Autodesk Fusion 360 part; units mm, degrees
(part 2 of 2)
equation "lin_gap_Ref = 4 mm" comment "ASSUMPTION: PM ruling pass C: gap above the upper side linings so they stay floating (= the 4 mm stack gap)"
equation "seam_gap_Ref = 2.26 mm" comment "DECIDED: PM ruling 2026-10-31 (Mechanical Checker F-001, F-005): the Joints Engineer's 2.26 mm at all nine site seam types, set by a metal stop (1.5 stop washer + 0.76 rivnut head; joints register section 2.8)"
equation "wall_z0_Ref = glide_h_Ref + band_h_Ref" comment "CALCULATION: base band top: glides + band"
equation "panel_z0_Ref = wall_z0_Ref + seam_gap_Ref" comment "CALCULATION: walls stand one seam_gap above the band top (joints register 2.8, IF-01)"
equation "wall_h_Ref = pod_h_Ref - wall_z0_Ref" comment "CALCULATION: 2290 = layout study v2_model wall_h"
equation "side_h_Ref = ( wall_h_Ref - 2 * seam_gap_Ref ) / 2" comment "CALCULATION: D-23: 2 sheets per side wall; the gap on the band and the horizontal seam (joints register 2.8)"
equation "back_oh_Ref = pod_h_Ref - outer_t_Ref - seam_gap_Ref - panel_z0_Ref" comment "CALCULATION: PM ruling 2026-10-31 (pass D, F-004): the back outer frames run up to the ceiling frame (pod_h - outer_t), less the seam_gap under it, closing the slot at the back top edge"
equation "back_ph_Ref = ( back_oh_Ref - seam_gap_Ref ) / 2" comment "CALCULATION: D-23: 4 sheets on the back, two equal rows with one seam_gap between them (joints register 2.8); the lower back linings match the lower row, as on the side walls"
equation "n_base_bolt_Ref = 4" comment "DECIDED: PM ruling 2026-10-31, J-BASE-01: bolts per panel along the band, evenly spaced"
equation "skin_t_Ref = 3 mm" comment "DECIDED: ACP skin, walls and ceiling (D-16; PM ruling 2026-10-31 on outer_t)"
equation "bond_t_Ref = 3 mm" comment "DECIDED: bond line between the ACP and the frame (PM ruling 2026-10-31 on outer_t)"
equation "frame_t_Ref = 40 mm" comment "DECIDED: aluminium frame tube depth, walls and ceiling (PM ruling 2026-10-31 on outer_t)"
equation "bolt_edge_inset_Ref = 220 mm" comment "DECIDED: PM ruling 2026-10-31: on every bolted edge the end bolts sit this far in from each panel end (the FRAME end, where the bolts go), the rest evenly spaced"
equation "spigot_inset_Ref = 100 mm" comment "DECIDED: PM ruling 2026-10-31: locating spigots this far in from each panel end (round hole at one end, slot at the other)"
equation "ceil_bolt_z_Ref = pod_h_Ref - outer_t_Ref + frame_t_Ref / 2" comment "DECIDED: PM ruling 2026-10-31, J-CEIL-01 wall to ceiling: the bolt line on the ceiling frame's centre (Z 2374)"
equation "pod_w = pod_w_Ref" comment "LINKED: pod_w_Ref, derived from 100000_P04_POD-SKELETON_CAD v4 (skeleton is the single source)"
equation "pod_d = pod_d_Ref" comment "LINKED: pod_d_Ref, derived from 100000_P04_POD-SKELETON_CAD v4 (skeleton is the single source)"
equation "pod_h = pod_h_Ref" comment "LINKED: pod_h_Ref, derived from 100000_P04_POD-SKELETON_CAD v4 (skeleton is the single source)"
equation "wall_depth = wall_depth_Ref" comment "LINKED: wall_depth_Ref, derived from 100000_P04_POD-SKELETON_CAD v4 (skeleton is the single source)"
equation "wall_z0 = wall_z0_Ref" comment "LINKED: wall_z0_Ref, derived from 100000_P04_POD-SKELETON_CAD v4 (skeleton is the single source)"
equation "panel_z0 = panel_z0_Ref" comment "LINKED: panel_z0_Ref, derived from 100000_P04_POD-SKELETON_CAD v4 (skeleton is the single source)"
equation "side_h = side_h_Ref" comment "LINKED: side_h_Ref, derived from 100000_P04_POD-SKELETON_CAD v4 (skeleton is the single source)"
equation "back_ph = back_ph_Ref" comment "LINKED: back_ph_Ref, derived from 100000_P04_POD-SKELETON_CAD v4 (skeleton is the single source)"
equation "stack_t = stack_t_Ref" comment "LINKED: stack_t_Ref, derived from 100000_P04_POD-SKELETON_CAD v4 (skeleton is the single source)"
equation "outer_t = outer_t_Ref" comment "LINKED: outer_t_Ref, derived from 100000_P04_POD-SKELETON_CAD v4 (skeleton is the single source)"
equation "cass_t = cass_t_Ref" comment "LINKED: cass_t_Ref, derived from 100000_P04_POD-SKELETON_CAD v4 (skeleton is the single source)"
equation "lin_gap = lin_gap_Ref" comment "LINKED: lin_gap_Ref, derived from 100000_P04_POD-SKELETON_CAD v4 (skeleton is the single source)"
equation "seam_gap = seam_gap_Ref" comment "LINKED: seam_gap_Ref, derived from 100000_P04_POD-SKELETON_CAD v4 (skeleton is the single source)"
equation "skin_t = skin_t_Ref" comment "LINKED: skin_t_Ref, derived from 100000_P04_POD-SKELETON_CAD v4 (skeleton is the single source)"
equation "bond_t = bond_t_Ref" comment "LINKED: bond_t_Ref, derived from 100000_P04_POD-SKELETON_CAD v4 (skeleton is the single source)"
equation "bolt_edge_inset = bolt_edge_inset_Ref" comment "LINKED: bolt_edge_inset_Ref, derived from 100000_P04_POD-SKELETON_CAD v4 (skeleton is the single source)"
equation "spigot_inset = spigot_inset_Ref" comment "LINKED: spigot_inset_Ref, derived from 100000_P04_POD-SKELETON_CAD v4 (skeleton is the single source)"
equation "n_base_bolt = n_base_bolt_Ref" comment "LINKED: n_base_bolt_Ref, derived from 100000_P04_POD-SKELETON_CAD v4 (skeleton is the single source)"
equation "ceil_bolt_z = ceil_bolt_z_Ref" comment "LINKED: ceil_bolt_z_Ref, derived from 100000_P04_POD-SKELETON_CAD v4 (skeleton is the single source)"
equation "tube_w = 20 mm" comment "CONFIRMED: D-34, D-54: aluminium tube 20 x 40 x 1.2; the 20 mm face carries the skin, so the 40 mm runs through the wall (outer_t = ACP 3 + frame 40). The joint register may turn it for the bond width (HOLD)"
equation "tube_d = outer_t - skin_t - bond_t" comment "CALCULATION: frame depth = outer panel 46 - skin 3 - bond 3 = 40 (D-34)"
equation "tube_t = 1.2 mm" comment "CONFIRMED: D-34, D-54, D-85: perimeter members (rails, front and back stiles) keep the 1.2 mm wall; they carry the rivnuts (grip check passed)"
equation "stud_t = 1.0 mm" comment "CONFIRMED: D-85 (weight): intermediate studs at a 1.0 mm wall; they carry no rivnut, only the skin's bond line"
equation "stile_pitch_max = 400 mm" comment "CONFIRMED: D-16, D-34: members 400 mm apart or less, to keep the ACP flat"
equation "pnl_len = wall_depth - seam_gap" comment "CALCULATION: D-49 depth 1495 less the 2.26 gap at the decor back plate (PM ruling on F-008): 1492.74"
equation "pnl_h = side_h" comment "CALCULATION: skeleton side_h: 2 sheets per side wall (D-23) with the seam gaps"
equation "skin_ret = outer_t - skin_t" comment "ASSUMPTION: back return of the side skin: covers the frame's back end at the corner, where the side skin covers the back panel's edge (D-55; sample drawing D04). V-groove and fold per the ACP maker (HOLD H16)"
equation "skin_setback = 0 mm" comment "ASSUMPTION: skin edge set back from the frame's top and bottom edges: 0, so the outside reveal equals the 2.26 seam gap (D-23: crisp, aligned reveals; joints register 2.8 leaves the setback to the WALL drawing)"
equation "frm_len = pnl_len - skin_t" comment "CALCULATION: the frame stops at the inside of the skin's back return"
equation "frm_h = pnl_h" comment "ASSUMPTION: the frame fills the skeleton envelope height; seam and base gasket gaps are set by the joint register (HOLD)"
equation "corner_w = 40 mm" comment "CONFIRMED: the side panel's back member is 40 x 40 x 1.2 (PM ruling on the joints register, item 3, 2026-10-31; register F2, FR-06): the back corner joint needs a 37+ mm overlap for the rivnut and the bolt"
equation "stile_n_mid = ceil(( frm_len - tube_w / 2 - corner_w / 2 ) / stile_pitch_max) - 1" comment "CALCULATION: intermediate stiles so that no stile pitch (centre to centre) exceeds stile_pitch_max"
equation "stile_pitch = ( frm_len - tube_w / 2 - corner_w / 2 ) / ( stile_n_mid + 1 )" comment "CALCULATION: equal stile pitch, centre to centre, from the front stile to the 40 mm back stile"
equation "top_h = tube_w" comment "CALCULATION: top member height: 20 on a lower panel; 40 x 40 on an upper panel, where the ceiling bolts in (PM ruling R-J3, joints register FR-06)"
equation "stile_len = frm_h - tube_w - top_h" comment "CALCULATION: stiles fit between the full-length rails (butt joints)"
equation "ceil_bolt_dz = pod_h - ceil_bolt_z" comment "CALCULATION: J-CEIL-01 side bolts on the ceiling frame tube's centre: the skeleton's ceil_bolt_z, Z 2374 on P04 (joints register R-J15, FR-07)"
equation "fill_t = tube_d" comment "CALCULATION: 40 mm PET fill fills the frame depth (D-34; layout study 40 mm)"
equation "bolt_d = 7 mm" comment "CONFIRMED: PM ruling on F-009: bolt holes 7.0 (0.51 float), position tolerance 0.4 (+-0.2) from the spigot hole, CNC or drill jig (joints register FR-02)"
equation "access_d = 19 mm" comment "CALCULATION: register FR-03: passes the 18 mm head washer (ISO 7093-1, R-J10), the M6 head and the 5 mm key; holds the grommet retainer (H-02)"
equation "bolt_line_y = pod_d / 2 - skin_t - bond_t - tube_d / 2" comment "CONFIRMED: J-WALL-02 bolt line on the back panel's tube centre, Y 824 (joints register R-J15, FR-07)"
equation "rivnut_d = 9.53 mm" comment "SOURCE: Sherex CAH3-610-4.2 hole 9.53 +0.10 (HW-SEL A5; register H-03)"
equation "spigot_d = 8.5 mm" comment "ASSUMPTION: register FR-05: hole for the 8 mm locating spigot H-05"
equation "spigot_slot = 14 mm" comment "ASSUMPTION: register FR-05: slot length for the second spigot"
equation "spigot_edge = spigot_inset" comment "CALCULATION: the skeleton's spigot_inset: spigots 100 from each end of the edge (PM ruling 2026-10-31, R-J13)"
equation "bolt_edge = bolt_edge_inset" comment "CALCULATION: the skeleton's bolt_edge_inset: end bolts 220 in from the panel's ends, evenly spaced, every bolt 30 or more from any stile (PM ruling 2026-10-31, R-J14)"
equation "n_side_jnt = 3" comment "SOURCE: register J-WALL-02, J-FRONT-01: 3 bolts up each side panel"
equation "side_jnt_pitch = ( pnl_h - 2 * bolt_edge ) / ( n_side_jnt - 1 )" comment "CALCULATION: equal pitch of the 3 bolts up the corner and decor joints"
equation "pocket_w = 60 mm" comment "ASSUMPTION: register FR-10: fill left out 60 x 60 next to each bolt for the key"
equation "corner_z0 = panel_z0" comment "CALCULATION: bottom of the back panel row this side panel meets at the corner (B1/B2 or B3/B4, skeleton P04)"
equation "corner_bolt_pitch = ( back_ph - 2 * bolt_edge ) / ( n_side_jnt - 1 )" comment "CALCULATION: J-WALL-02 bolts run along the back panel's edge: 220, 559.31, 898.61 on its 1118.61 (joints register 2.9)"
equation "n_len_bolt = n_base_bolt" comment "CALCULATION: the skeleton's n_base_bolt (4): the same count on J-WALL-01 and the J-CEIL-01 side edges (register 2.9)"
equation "ceil_bolt_pitch = ( wall_depth - 2 * bolt_edge ) / ( n_len_bolt - 1 )" comment "CALCULATION: J-CEIL-01 side edge: 4 bolts along the ceiling's 1495 from Y -645 (its front edge), 220 rule, pitch 351.67 on P04; CEILING drills the same (PM ruling 2026-10-31 16:55; joints register 2.9)"
equation "len_bolt_pitch = ( pnl_len - 2 * bolt_edge ) / ( n_len_bolt - 1 )" comment "CALCULATION: even pitch of the bolts along the panel"
equation "felt_t = 9 mm" comment "SOURCE: plan VT03-PET 9 mm PET felt; HW-SEL A3; D-31 (the factory's felt)"
equation "tray_t = 0.5 mm" comment "CONFIRMED: D-37: galvanised steel tray 0.5 mm"
equation "tray_h = cass_t" comment "CONFIRMED: PM ruling 2026-10-31 (WALL group, option 1): the wall cassettes use the ceiling's tray, returns the full cassette depth (34) turned in as lips that hold the felt, no ribs; settles H09 for the walls"
equation "lip_w = 12 mm" comment "CONFIRMED: PM ruling 2026-10-31 (WALL group, option 1): 12 mm lips hold the felt edge"
equation "bend_r = tray_t" comment "ASSUMPTION: inside bend radius 1 x t for 0.5 mm DX51D (the sheet metal rule's bend radius is its Thickness); the factory's tooling sets it (guideline 9)"
equation "felt_c = 1 mm" comment "ASSUMPTION: felt edge clearance inside the returns, as the ceiling cassette"
equation "gap_h = tray_h - felt_t - 2 * tray_t" comment "CALCULATION: air gap between the tray base and the felt (24): the acoustic gap (D-17) and the cable path (D-26)"
equation "cass_len = wall_depth - stack_t + cass_t" comment "CALCULATION: = 1448: from the decor back plate to past the back cassette's face, closing the inside corner (D-57)"
equation "cass_h = side_h" comment "CALCULATION: lower: the panel height; upper: stops lin_gap under the roof frame so it floats (D-57)"
equation "clip_zone_h = 60 mm" comment "ASSUMPTION: height of each reserved clip zone (H03: no clip named)"
equation "clip_zone_dz = 100 mm" comment "ASSUMPTION: clip zone centre from the cassette's top and bottom edges (H03)"
equation "stopw_od = 20 mm" comment "SOURCE: joints register H-08: stop washer Ø10.5 x Ø20 x 1.5 (PROPOSED part)"
equation "stopw_id = 10.5 mm" comment "SOURCE: joints register H-08"
equation "stopw_t = 1.5 mm" comment "SOURCE: joints register H-08: rivnut head 0.76 + washer 1.5 = the 2.26 stop (R-J5)"
equation "rivnut_head_d = 12.96 mm" comment "SOURCE: Sherex CAH3-610-4.2 head Ø12.96 (joints register H-03, SHX)"
equation "rivnut_head_t = 0.76 mm" comment "SOURCE: Sherex CAH3-610-4.2 head 0.76 ±0.08 (H-03, SHX)"
equation "rivnut_body_d = 9.5 mm" comment "SOURCE: Sherex CAH3-610-4.2 body Ø9.50 max (H-03, SHX)"
equation "rivnut_len = 10.16 mm" comment "SOURCE: Sherex CAH3-610-4.2 installed length 10.16 max under the head (H-03, SHX); the bulge inside the tube is not modelled"
equation "m6_d = 6 mm" comment "CALCULATION: M6 threads shown at their 6 mm major diameter (no modelled thread)"
equation "spigot_pin_d = 8 mm" comment "SOURCE: joints register H-05: Ø8 stainless pin (PROPOSED, assumption sizes)"
equation "spigot_proud = 8 mm" comment "SOURCE: joints register H-05: stands 8 proud (read as: of the joint face)"
equation "spigot_thread_l = 10 mm" comment "ASSUMPTION: M6 thread into the spigot rivnut; H-05 gives no length; 10 stays inside the rivnut's 10.16"
equation "d165 = panel_z0"
equation "d167 = ( ( pod_w / 2 - skin_t - bond_t ) ) - ( ( pod_w / 2 - outer_t ) )"
equation "d168 = ( pod_d / 2 - skin_t ) - ( pod_d / 2 - wall_depth + seam_gap )"
equation "d169 = abs(( pod_w / 2 - outer_t ))"
equation "d170 = abs(pod_d / 2 - wall_depth + seam_gap)"
equation "d171 = ( ( panel_z0 ) + tube_w ) - ( panel_z0 )"
equation "d173 = ( panel_z0 ) + tube_t"
equation "d175 = ( ( ( pod_w / 2 - skin_t - bond_t ) ) - tube_t ) - ( ( ( pod_w / 2 - outer_t ) ) + tube_t )"
equation "d176 = ( pod_d / 2 - skin_t ) - ( pod_d / 2 - wall_depth + seam_gap )"
equation "d177 = abs(( ( pod_w / 2 - outer_t ) ) + tube_t)"
equation "d178 = abs(pod_d / 2 - wall_depth + seam_gap)"
equation "d179 = ( ( ( panel_z0 ) + tube_w ) - tube_t ) - ( ( panel_z0 ) + tube_t )"
equation "d181 = ( panel_z0 + side_h ) - top_h"
equation "d183 = ( ( pod_w / 2 - skin_t - bond_t ) ) - ( ( pod_w / 2 - outer_t ) )"
equation "d184 = ( pod_d / 2 - skin_t ) - ( pod_d / 2 - wall_depth + seam_gap )"
equation "d185 = abs(( pod_w / 2 - outer_t ))"
equation "d186 = abs(pod_d / 2 - wall_depth + seam_gap)"
equation "d187 = ( panel_z0 + side_h ) - ( ( panel_z0 + side_h ) - top_h )"
equation "d189 = ( ( panel_z0 + side_h ) - top_h ) + tube_t"
equation "d191 = ( ( ( pod_w / 2 - skin_t - bond_t ) ) - tube_t ) - ( ( ( pod_w / 2 - outer_t ) ) + tube_t )"
equation "d192 = ( pod_d / 2 - skin_t ) - ( pod_d / 2 - wall_depth + seam_gap )"
equation "d193 = abs(( ( pod_w / 2 - outer_t ) ) + tube_t)"
equation "d194 = abs(pod_d / 2 - wall_depth + seam_gap)"
equation "d195 = ( ( panel_z0 + side_h ) - tube_t ) - ( ( ( panel_z0 + side_h ) - top_h ) + tube_t )"
equation "d197 = ( panel_z0 ) + tube_w"
equation "d199 = ( ( pod_w / 2 - skin_t - bond_t ) ) - ( ( pod_w / 2 - outer_t ) )"
equation "d200 = ( ( pod_d / 2 - wall_depth + seam_gap ) + tube_w ) - ( pod_d / 2 - wall_depth + seam_gap )"
equation "d201 = abs(( pod_w / 2 - outer_t ))"
equation "d202 = abs(pod_d / 2 - wall_depth + seam_gap)"
equation "d203 = ( ( panel_z0 + side_h ) - top_h ) - ( ( panel_z0 ) + tube_w )"
equation "d205 = ( panel_z0 ) + tube_w"
equation "d207 = ( ( ( pod_w / 2 - skin_t - bond_t ) ) - tube_t ) - ( ( ( pod_w / 2 - outer_t ) ) + tube_t )"
equation "d208 = ( ( ( pod_d / 2 - wall_depth + seam_gap ) + tube_w ) - tube_t ) - ( ( pod_d / 2 - wall_depth + seam_gap ) + tube_t )"
equation "d209 = abs(( ( pod_w / 2 - outer_t ) ) + tube_t)"
equation "d210 = abs(( pod_d / 2 - wall_depth + seam_gap ) + tube_t)"
equation "d211 = ( ( panel_z0 + side_h ) - top_h ) - ( ( panel_z0 ) + tube_w )"
equation "d213 = ( panel_z0 ) + tube_w"
equation "d215 = ( ( pod_w / 2 - skin_t - bond_t ) ) - ( ( pod_w / 2 - outer_t ) )"
equation "d216 = ( pod_d / 2 - skin_t ) - ( ( pod_d / 2 - skin_t ) - corner_w )"
equation "d217 = abs(( pod_w / 2 - outer_t ))"
equation "d218 = abs(( pod_d / 2 - skin_t ) - corner_w)"
equation "d219 = ( ( panel_z0 + side_h ) - top_h ) - ( ( panel_z0 ) + tube_w )"
equation "d221 = ( panel_z0 ) + tube_w"
equation "d223 = ( ( ( pod_w / 2 - skin_t - bond_t ) ) - tube_t ) - ( ( ( pod_w / 2 - outer_t ) ) + tube_t )"
equation "d224 = ( ( pod_d / 2 - skin_t ) - tube_t ) - ( ( ( pod_d / 2 - skin_t ) - corner_w ) + tube_t )"
equation "d225 = abs(( ( pod_w / 2 - outer_t ) ) + tube_t)"
equation "d226 = abs(( ( pod_d / 2 - skin_t ) - corner_w ) + tube_t)"
equation "d227 = ( ( panel_z0 + side_h ) - top_h ) - ( ( panel_z0 ) + tube_w )"
equation "d229 = ( panel_z0 ) + tube_w"
equation "d231 = ( ( pod_w / 2 - skin_t - bond_t ) ) - ( ( pod_w / 2 - outer_t ) )"
equation "d232 = ( ( pod_d / 2 - wall_depth + seam_gap ) + stile_pitch + tube_w ) - ( ( pod_d / 2 - wall_depth + seam_gap ) + stile_pitch )"
equation "d233 = abs(( pod_w / 2 - outer_t ))"
equation "d234 = abs(( pod_d / 2 - wall_depth + seam_gap ) + stile_pitch)"
equation "d235 = ( ( panel_z0 + side_h ) - top_h ) - ( ( panel_z0 ) + tube_w )"
equation "d237 = ( panel_z0 ) + tube_w"
equation "d239 = ( ( ( pod_w / 2 - skin_t - bond_t ) ) - stud_t ) - ( ( ( pod_w / 2 - outer_t ) ) + stud_t )"
equation "d240 = ( ( ( pod_d / 2 - wall_depth + seam_gap ) + stile_pitch + tube_w ) - stud_t ) - ( ( ( pod_d / 2 - wall_depth + seam_gap ) + stile_pitch ) + stud_t )"
equation "d241 = abs(( ( pod_w / 2 - outer_t ) ) + stud_t)"
equation "d242 = abs(( ( pod_d / 2 - wall_depth + seam_gap ) + stile_pitch ) + stud_t)"
equation "d243 = ( ( panel_z0 + side_h ) - top_h ) - ( ( panel_z0 ) + tube_w )"
equation "d245 = stile_n_mid"
equation "d247 = stile_pitch"
equation "d249 = ( panel_z0 ) + skin_setback"
equation "d251 = ( ( pod_w / 2 ) ) - ( ( pod_w / 2 - skin_t ) )"
equation "d252 = ( pod_d / 2 ) - ( pod_d / 2 - wall_depth + seam_gap )"
equation "d253 = abs(( pod_w / 2 - skin_t ))"
equation "d254 = abs(pod_d / 2 - wall_depth + seam_gap)"
equation "d255 = ( ( panel_z0 + side_h ) - skin_setback ) - ( ( panel_z0 ) + skin_setback )"
equation "d257 = ( panel_z0 ) + skin_setback"
equation "d259 = ( ( pod_w / 2 - skin_t ) ) - ( ( pod_w / 2 - skin_t - skin_ret ) )"
equation "d260 = ( pod_d / 2 ) - ( pod_d / 2 - skin_t )"
equation "d261 = abs(( pod_w / 2 - skin_t - skin_ret ))"
equation "d262 = abs(pod_d / 2 - skin_t)"
equation "d263 = ( ( panel_z0 + side_h ) - skin_setback ) - ( ( panel_z0 ) + skin_setback )"
equation "d265 = ( panel_z0 ) + tube_w"
equation "d267 = ( ( pod_w / 2 - skin_t - bond_t ) ) - ( ( pod_w / 2 - outer_t ) )"
equation "d268 = ( ( pod_d / 2 - wall_depth + seam_gap ) + stile_pitch ) - ( ( pod_d / 2 - wall_depth + seam_gap ) + tube_w )"
equation "d269 = abs(( pod_w / 2 - outer_t ))"
equation "d270 = abs(( pod_d / 2 - wall_depth + seam_gap ) + tube_w)"
equation "d271 = ( ( panel_z0 + side_h ) - top_h ) - ( ( panel_z0 ) + tube_w )"
equation "d273 = stile_n_mid"
equation "d275 = stile_pitch"
equation "d277 = ( panel_z0 ) + tube_w"
equation "d279 = ( ( pod_w / 2 - skin_t - bond_t ) ) - ( ( pod_w / 2 - outer_t ) )"
equation "d280 = ( ( pod_d / 2 - skin_t ) - corner_w ) - ( ( pod_d / 2 - wall_depth + seam_gap ) + stile_n_mid * stile_pitch + tube_w )"
equation "d281 = abs(( pod_w / 2 - outer_t ))"
equation "d282 = abs(( pod_d / 2 - wall_depth + seam_gap ) + stile_n_mid * stile_pitch + tube_w)"
equation "d283 = ( ( panel_z0 + side_h ) - top_h ) - ( ( panel_z0 ) + tube_w )"
equation "d285 = ( panel_z0 ) + tube_w"
equation "d287 = ( ( pod_w / 2 - skin_t - bond_t ) ) - ( ( pod_w / 2 - outer_t ) )"
equation "d288 = ( ( ( pod_d / 2 - wall_depth + seam_gap ) + bolt_edge + 0 * len_bolt_pitch ) + pocket_w / 2 ) - ( ( ( pod_d / 2 - wall_depth + seam_gap ) + bolt_edge + 0 * len_bolt_pitch ) - pocket_w / 2 )"
equation "d289 = abs(( pod_w / 2 - outer_t ))"
equation "d290 = abs(( ( pod_d / 2 - wall_depth + seam_gap ) + bolt_edge + 0 * len_bolt_pitch ) - pocket_w / 2)"
equation "d291 = ( ( ( panel_z0 ) + tube_w ) + pocket_w ) - ( ( panel_z0 ) + tube_w )"
equation "d293 = ( panel_z0 ) + tube_w"
equation "d295 = ( ( pod_w / 2 - skin_t - bond_t ) ) - ( ( pod_w / 2 - outer_t ) )"
equation "d296 = ( ( ( pod_d / 2 - wall_depth + seam_gap ) + bolt_edge + 1 * len_bolt_pitch ) + pocket_w / 2 ) - ( ( ( pod_d / 2 - wall_depth + seam_gap ) + bolt_edge + 1 * len_bolt_pitch ) - pocket_w / 2 )"
equation "d297 = abs(( pod_w / 2 - outer_t ))"
equation "d298 = abs(( ( pod_d / 2 - wall_depth + seam_gap ) + bolt_edge + 1 * len_bolt_pitch ) - pocket_w / 2)"
equation "d299 = ( ( ( panel_z0 ) + tube_w ) + pocket_w ) - ( ( panel_z0 ) + tube_w )"
equation "d301 = ( panel_z0 ) + tube_w"
equation "d303 = ( ( pod_w / 2 - skin_t - bond_t ) ) - ( ( pod_w / 2 - outer_t ) )"
equation "d304 = ( ( ( pod_d / 2 - wall_depth + seam_gap ) + bolt_edge + 2 * len_bolt_pitch ) + pocket_w / 2 ) - ( ( ( pod_d / 2 - wall_depth + seam_gap ) + bolt_edge + 2 * len_bolt_pitch ) - pocket_w / 2 )"
equation "d305 = abs(( pod_w / 2 - outer_t ))"
equation "d306 = abs(( ( pod_d / 2 - wall_depth + seam_gap ) + bolt_edge + 2 * len_bolt_pitch ) - pocket_w / 2)"
equation "d307 = ( ( ( panel_z0 ) + tube_w ) + pocket_w ) - ( ( panel_z0 ) + tube_w )"
equation "d309 = ( panel_z0 ) + tube_w"
equation "d311 = ( ( pod_w / 2 - skin_t - bond_t ) ) - ( ( pod_w / 2 - outer_t ) )"
equation "d312 = ( ( ( pod_d / 2 - wall_depth + seam_gap ) + bolt_edge + 3 * len_bolt_pitch ) + pocket_w / 2 ) - ( ( ( pod_d / 2 - wall_depth + seam_gap ) + bolt_edge + 3 * len_bolt_pitch ) - pocket_w / 2 )"
equation "d313 = abs(( pod_w / 2 - outer_t ))"
equation "d314 = abs(( ( pod_d / 2 - wall_depth + seam_gap ) + bolt_edge + 3 * len_bolt_pitch ) - pocket_w / 2)"
equation "d315 = ( ( ( panel_z0 ) + tube_w ) + pocket_w ) - ( ( panel_z0 ) + tube_w )"
equation "d317 = ( ( ( panel_z0 ) + bolt_edge ) + 0 * side_jnt_pitch ) - pocket_w / 2"
equation "d319 = ( ( pod_w / 2 - skin_t - bond_t ) ) - ( ( pod_w / 2 - outer_t ) )"
equation "d320 = ( ( pod_d / 2 - wall_depth + seam_gap ) + tube_w + pocket_w ) - ( ( pod_d / 2 - wall_depth + seam_gap ) + tube_w )"
equation "d321 = abs(( pod_w / 2 - outer_t ))"
equation "d322 = abs(( pod_d / 2 - wall_depth + seam_gap ) + tube_w)"
equation "d323 = ( ( ( ( panel_z0 ) + bolt_edge ) + 0 * side_jnt_pitch ) + pocket_w / 2 ) - ( ( ( ( panel_z0 ) + bolt_edge ) + 0 * side_jnt_pitch ) - pocket_w / 2 )"
equation "d325 = ( ( ( panel_z0 ) + bolt_edge ) + 1 * side_jnt_pitch ) - pocket_w / 2"
equation "d327 = ( ( pod_w / 2 - skin_t - bond_t ) ) - ( ( pod_w / 2 - outer_t ) )"
equation "d328 = ( ( pod_d / 2 - wall_depth + seam_gap ) + tube_w + pocket_w ) - ( ( pod_d / 2 - wall_depth + seam_gap ) + tube_w )"
equation "d329 = abs(( pod_w / 2 - outer_t ))"
equation "d330 = abs(( pod_d / 2 - wall_depth + seam_gap ) + tube_w)"
equation "d331 = ( ( ( ( panel_z0 ) + bolt_edge ) + 1 * side_jnt_pitch ) + pocket_w / 2 ) - ( ( ( ( panel_z0 ) + bolt_edge ) + 1 * side_jnt_pitch ) - pocket_w / 2 )"
equation "d333 = ( ( ( panel_z0 ) + bolt_edge ) + 2 * side_jnt_pitch ) - pocket_w / 2"
equation "d335 = ( ( pod_w / 2 - skin_t - bond_t ) ) - ( ( pod_w / 2 - outer_t ) )"
equation "d336 = ( ( pod_d / 2 - wall_depth + seam_gap ) + tube_w + pocket_w ) - ( ( pod_d / 2 - wall_depth + seam_gap ) + tube_w )"
equation "d337 = abs(( pod_w / 2 - outer_t ))"
equation "d338 = abs(( pod_d / 2 - wall_depth + seam_gap ) + tube_w)"
equation "d339 = ( ( ( ( panel_z0 ) + bolt_edge ) + 2 * side_jnt_pitch ) + pocket_w / 2 ) - ( ( ( ( panel_z0 ) + bolt_edge ) + 2 * side_jnt_pitch ) - pocket_w / 2 )"
equation "d341 = panel_z0"
equation "d343 = abs(( pod_w / 2 - skin_t - bond_t - tube_d / 2 ))"
equation "d344 = abs(( pod_d / 2 - wall_depth + seam_gap ) + bolt_edge)"
equation "d345 = tube_t"
equation "d346 = bolt_d"
equation "d348 = ( panel_z0 ) + tube_w"
equation "d350 = abs(( pod_w / 2 - skin_t - bond_t - tube_d / 2 ))"
equation "d351 = abs(( pod_d / 2 - wall_depth + seam_gap ) + bolt_edge)"
equation "d352 = tube_t"
equation "d353 = access_d"
equation "d355 = n_len_bolt"
equation "d357 = len_bolt_pitch"
equation "d359 = panel_z0"
equation "d361 = abs(( pod_w / 2 - skin_t - bond_t - tube_d / 2 ))"
equation "d362 = abs(( pod_d / 2 - wall_depth + seam_gap ) + spigot_edge)"
equation "d363 = tube_t"
equation "d364 = spigot_d"
equation "d366 = panel_z0"
equation "d368 = ( ( ( pod_w / 2 - skin_t - bond_t - tube_d / 2 ) ) + ( spigot_slot - spigot_d ) / 2 ) - ( ( ( pod_w / 2 - skin_t - bond_t - tube_d / 2 ) ) - ( spigot_slot - spigot_d ) / 2 )"
equation "d369 = ( ( ( pod_d / 2 ) - spigot_edge ) + spigot_d / 2 ) - ( ( ( pod_d / 2 ) - spigot_edge ) - spigot_d / 2 )"
equation "d370 = abs(( ( pod_w / 2 - skin_t - bond_t - tube_d / 2 ) ) - ( spigot_slot - spigot_d ) / 2)"
equation "d371 = abs(( ( pod_d / 2 ) - spigot_edge ) - spigot_d / 2)"
equation "d372 = ( ( panel_z0 ) + tube_t ) - ( panel_z0 )"
equation "d374 = panel_z0"
equation "d376 = abs(( ( pod_w / 2 - skin_t - bond_t - tube_d / 2 ) ) - ( spigot_slot - spigot_d ) / 2)"
equation "d377 = abs(( pod_d / 2 ) - spigot_edge)"
equation "d378 = tube_t"
equation "d379 = spigot_d"
equation "d381 = panel_z0"
equation "d383 = abs(( ( pod_w / 2 - skin_t - bond_t - tube_d / 2 ) ) + ( spigot_slot - spigot_d ) / 2)"
equation "d384 = abs(( pod_d / 2 ) - spigot_edge)"
equation "d385 = tube_t"
equation "d386 = spigot_d"
equation "d388 = panel_z0 + side_h"
equation "d390 = abs(( pod_w / 2 - skin_t - bond_t - tube_d / 2 ))"
equation "d391 = abs(( pod_d / 2 - wall_depth + seam_gap ) + bolt_edge)"
equation "d392 = tube_t"
equation "d393 = rivnut_d"
equation "d395 = n_len_bolt"
equation "d397 = len_bolt_pitch"
equation "d399 = panel_z0 + side_h"
equation "d401 = abs(( pod_w / 2 - skin_t - bond_t - tube_d / 2 ))"
equation "d402 = abs(( pod_d / 2 - wall_depth + seam_gap ) + spigot_edge)"
equation "d403 = tube_t"
equation "d404 = rivnut_d"
equation "d406 = panel_z0 + side_h"
equation "d408 = abs(( pod_w / 2 - skin_t - bond_t - tube_d / 2 ))"
equation "d409 = abs(( pod_d / 2 ) - spigot_edge)"
equation "d410 = tube_t"
equation "d411 = rivnut_d"
equation "d413 = pod_d / 2 - wall_depth + seam_gap"
equation "d415 = abs(( pod_w / 2 - skin_t - bond_t - tube_d / 2 ))"
equation "d416 = abs(( panel_z0 ) + bolt_edge)"
equation "d417 = tube_t"
equation "d418 = bolt_d"
equation "d420 = ( pod_d / 2 - wall_depth + seam_gap ) + tube_w"
equation "d422 = abs(( pod_w / 2 - skin_t - bond_t - tube_d / 2 ))"
equation "d423 = abs(( panel_z0 ) + bolt_edge)"
equation "d424 = tube_t"
equation "d425 = access_d"
equation "d427 = n_side_jnt"
equation "d429 = side_jnt_pitch"
equation "d431 = ( pod_w / 2 - outer_t )"
equation "d433 = abs(bolt_line_y)"
equation "d434 = abs(corner_z0 + bolt_edge)"
equation "d435 = tube_t"
equation "d436 = rivnut_d"
equation "d438 = n_side_jnt"
equation "d440 = corner_bolt_pitch"
equation "d442 = panel_z0 + side_h"
equation "d444 = abs(( pod_w / 2 - skin_t - bond_t - tube_d / 2 ))"
equation "d445 = abs(( pod_d / 2 - wall_depth + seam_gap ) + bolt_edge)"
equation "d446 = stopw_od"
equation "d447 = stopw_id"
equation "d448 = stopw_t"
equation "d450 = ( panel_z0 + side_h ) + stopw_t"
equation "d452 = abs(( pod_w / 2 - skin_t - bond_t - tube_d / 2 ))"
equation "d453 = abs(( pod_d / 2 - wall_depth + seam_gap ) + bolt_edge)"
equation "d454 = rivnut_head_d"
equation "d455 = m6_d"
equation "d456 = rivnut_head_t"
equation "d458 = ( panel_z0 + side_h ) + stopw_t"
equation "d460 = abs(( pod_w / 2 - skin_t - bond_t - tube_d / 2 ))"
equation "d461 = abs(( pod_d / 2 - wall_depth + seam_gap ) + bolt_edge)"
equation "d462 = rivnut_body_d"
equation "d463 = m6_d"
equation "d466 = -( rivnut_len )"
equation "d468 = n_len_bolt"
equation "d470 = len_bolt_pitch"
equation "d472 = n_len_bolt"
equation "d474 = len_bolt_pitch"
equation "d476 = panel_z0 + side_h"
equation "d478 = abs(( pod_w / 2 - skin_t - bond_t - tube_d / 2 ))"
equation "d479 = abs(( pod_d / 2 - wall_depth + seam_gap ) + spigot_edge)"
equation "d480 = rivnut_head_d"
equation "d481 = m6_d"
equation "d482 = rivnut_head_t"
equation "d484 = panel_z0 + side_h"
equation "d486 = abs(( pod_w / 2 - skin_t - bond_t - tube_d / 2 ))"
equation "d487 = abs(( pod_d / 2 - wall_depth + seam_gap ) + spigot_edge)"
equation "d488 = rivnut_body_d"
equation "d489 = m6_d"
equation "d492 = -( rivnut_len )"
equation "d494 = ( panel_z0 + side_h ) + rivnut_head_t"
equation "d496 = abs(( pod_w / 2 - skin_t - bond_t - tube_d / 2 ))"
equation "d497 = abs(( pod_d / 2 - wall_depth + seam_gap ) + spigot_edge)"
equation "d498 = spigot_pin_d"
equation "d499 = spigot_proud - rivnut_head_t"
equation "d501 = ( panel_z0 + side_h ) + rivnut_head_t"
equation "d503 = abs(( pod_w / 2 - skin_t - bond_t - tube_d / 2 ))"
equation "d504 = abs(( pod_d / 2 - wall_depth + seam_gap ) + spigot_edge)"
equation "d505 = m6_d"
equation "d508 = -( spigot_thread_l )"
equation "d510 = panel_z0 + side_h"
equation "d512 = abs(( pod_w / 2 - skin_t - bond_t - tube_d / 2 ))"
equation "d513 = abs(( pod_d / 2 ) - spigot_edge)"
equation "d514 = rivnut_head_d"
equation "d515 = m6_d"
equation "d516 = rivnut_head_t"
equation "d518 = panel_z0 + side_h"
equation "d520 = abs(( pod_w / 2 - skin_t - bond_t - tube_d / 2 ))"
equation "d521 = abs(( pod_d / 2 ) - spigot_edge)"
equation "d522 = rivnut_body_d"
equation "d523 = m6_d"
equation "d526 = -( rivnut_len )"
equation "d528 = ( panel_z0 + side_h ) + rivnut_head_t"
equation "d530 = abs(( pod_w / 2 - skin_t - bond_t - tube_d / 2 ))"
equation "d531 = abs(( pod_d / 2 ) - spigot_edge)"
equation "d532 = spigot_pin_d"
equation "d533 = spigot_proud - rivnut_head_t"
equation "d535 = ( panel_z0 + side_h ) + rivnut_head_t"
equation "d537 = abs(( pod_w / 2 - skin_t - bond_t - tube_d / 2 ))"
equation "d538 = abs(( pod_d / 2 ) - spigot_edge)"
equation "d539 = m6_d"
equation "d542 = -( spigot_thread_l )"
equation "d544 = ( pod_w / 2 - outer_t )"
equation "d546 = abs(bolt_line_y)"
equation "d547 = abs(corner_z0 + bolt_edge)"
equation "d548 = stopw_od"
equation "d549 = stopw_id"
equation "d552 = -( stopw_t )"
equation "d554 = ( ( pod_w / 2 - outer_t ) ) - stopw_t"
equation "d556 = abs(bolt_line_y)"
equation "d557 = abs(corner_z0 + bolt_edge)"
equation "d558 = rivnut_head_d"
equation "d559 = m6_d"
equation "d562 = -( rivnut_head_t )"
equation "d564 = ( ( pod_w / 2 - outer_t ) ) - stopw_t"
equation "d566 = abs(bolt_line_y)"
equation "d567 = abs(corner_z0 + bolt_edge)"
equation "d568 = rivnut_body_d"
equation "d569 = m6_d"
equation "d570 = rivnut_len"
equation "d572 = n_side_jnt"
equation "d574 = corner_bolt_pitch"
equation "d576 = n_side_jnt"
equation "d578 = corner_bolt_pitch"
named bodies: "RAIL - BOTTOM", "RAIL - TOP", "STILE - FRONT", "STILE - BACK", "STILE - MID 1", "STILE - MID 2", "STILE - MID 3", "SKIN - ACP 3 WITH BACK RETURN", "FILL - BAY 1", "FILL - BAY 2", "FILL - BAY 3", "FILL - BAY 4", "STOP WASHER - TOP RAIL 1", "RIVNUT - TOP RAIL 1", "STOP WASHER - TOP RAIL 2", "STOP WASHER - TOP RAIL 3", "STOP WASHER - TOP RAIL 4", "RIVNUT - TOP RAIL 2", "RIVNUT - TOP RAIL 3", "RIVNUT - TOP RAIL 4", "RIVNUT - TOP RAIL SPIGOT FRONT", "SPIGOT - TOP RAIL SPIGOT FRONT", "RIVNUT - TOP RAIL SPIGOT BACK", "SPIGOT - TOP RAIL SPIGOT BACK", "STOP WASHER - BACK STILE CORNER 1", "RIVNUT - BACK STILE CORNER 1", "STOP WASHER - BACK STILE CORNER 2", "STOP WASHER - BACK STILE CORNER 3", "RIVNUT - BACK STILE CORNER 2", "RIVNUT - BACK STILE CORNER 3"
